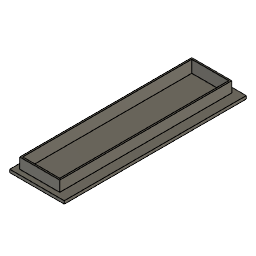
Lamp bracket cover (Autodesk Fusion 360 design; units mm, degrees)
Autodesk Fusion 360 part; units mm, degrees
sketch "Sketch1" plane through (0, 0, 0) normal (0, 0, 1) x (1, 0, 0)
  line L0 (0, 0) -> (18, 0)
  line L1 (18, 0) -> (18, 60)
  line L2 (18, 60) -> (0, 60)
  line L3 (0, 60) -> (0, 0)
  dimension "d1" = 18
  dimension "d2" = 60
  constraint horizontal L0
  constraint vertical L1
  constraint horizontal L2
  constraint vertical L3
  constraint coincident L0.start L3.end
  measures "d1" distance of L0.start L0.end
  measures "d2" distance of L0.start L2.end
extrude "Extrude1" add sketch "Sketch1" along normal blind 1
sketch "Sketch2" plane through (0, 0, 1) normal (0, 0, 1) x (-1, 0, 0)
  line L0 (0, -60) -> (0, 0)
  line L1 (0, 0) -> (-18, 0)
  line L2 (-18, 0) -> (-18, -60)
  line L3 (-18, -60) -> (0, -60)
  line L4 (-18, -58.5) -> (-15, -58.5)
  line L5 (-15, -60) -> (-15, -58.5)
  line L6 (-8.25, -58.5) -> (-8.25, -1.5)
  line L7 (-1.5, -30) -> (-15, -30)
  line L8 (-14.85, -1.65) -> (-1.65, -1.65)
  line L9 (-1.65, -1.65) -> (-1.65, -58.35)
  line L10 (-1.65, -58.35) -> (-14.85, -58.35)
  line L11 (-14.85, -58.35) -> (-14.85, -1.65)
  line L12 (-14.85, -1.65) -> (-1.65, -58.35) construction
  line L13 (-1.65, -1.65) -> (-14.85, -58.35) construction
  point P0 (-8.25, -30)
  dimension "d5" = 3
  dimension "d8" = 6.75
  dimension "d10" = 13.2
  dimension "d11" = 56.7
  constraint coincident L2 L4.start
  constraint perpendicular L2 L4
  constraint coincident L3 L5.start
  constraint horizontal L8
  constraint perpendicular L8 L9
  constraint parallel L8 L10
  constraint parallel L9 L11
  constraint coincident L12 P0
  constraint coincident L13 P0
  constraint midpoint L6 P0
  measures "d5" distance of L4.start L4.end
  measures "d8" distance of L4.end L6.start
  measures "d10" distance of L9.end L10.end
  measures "d11" distance of L8.end L9.end
extrude "Extrude2" add sketch "Sketch2" along normal blind 3.5 contours L6 L7 L10 L11 | L6 L7 L9 L10 | L6 L7 L8 L11 | L6 L7 L8 L9
shell "Shell1" thickness 0.5 removed faces 1 at (6.05, 39.45, 4.5)
equation "d8 = ( 13.500 / 2 ) * 1 mm"
